HomeMade2F140_v2 (Autodesk Fusion 360 design; units mm, degrees)
part number: 2026-10-15-15-43-31-036
part number: 2026-10-15-15-43-44-268
part number: 2026-10-15-15-43-45-165
part number: 2026-10-15-15-43-48-577
part number: 2026-10-15-15-43-49-111
part number: 2026-10-15-15-43-49-328
part number: 2026-10-15-15-43-49-848
part number: 2026-10-15-15-43-50-479
part number: 2026-10-15-15-43-52-016
part number: 2026-10-15-15-43-53-608
part number: 2026-10-15-15-43-55-090
part number: 2026-10-15-15-43-57-573
part number: 2026-10-15-15-43-59-187
part number: 2026-10-15-15-44-01-030
part number: 2026-10-15-15-44-07-533
part number: 2026-10-15-15-44-10-409
part number: 2026-10-15-15-44-15-954
Autodesk Fusion 360 part; units mm, degrees
(part 1 of 3)
ref_plane "WorkPlane1" through (-36, 0, 0) normal (1, 0, 0) x (0, 1, 0) in component "Tower"
sketch "X00_add_rect" plane through (-36, 0, 0) normal (1, 0, 0) x (0, 0, -1) in component "Tower"
  line L0 (-36, -40.5) -> (-36, 40.5)
  line L1 (-36, 40.5) -> (-40, 40.5)
  line L2 (-40, 40.5) -> (-40, -40.5)
  line L3 (-40, -40.5) -> (-36, -40.5)
extrude "X00_add_rect (1)" add sketch "X00_add_rect" along normal blind 70 makes body 1 in component "Tower"
ref_plane "WorkPlane2" through (-5.25, 0, 0) normal (1, 0, 0) x (0, 1, 0) in component "Tower"
sketch "X01_cut_rect" plane through (-5.25, 0, 0) normal (1, 0, 0) x (0, 0, -1) in component "Tower"
  line L0 (-35, -26) -> (-35, 26)
  line L1 (-35, 26) -> (-41, 26)
  line L2 (-41, 26) -> (-41, -26)
  line L3 (-41, -26) -> (-35, -26)
extrude "X01_cut_rect (1)" cut sketch "X01_cut_rect" along normal blind 10.5 bodies 1 in component "Tower"
ref_plane "WorkPlane3" through (18.75, 0, 0) normal (1, 0, 0) x (0, 1, 0) in component "Tower"
sketch "X02_cut_rect" plane through (18.75, 0, 0) normal (1, 0, 0) x (0, 0, -1) in component "Tower"
  line L0 (-35, -37) -> (-35, -21)
  line L1 (-35, -21) -> (-41, -21)
  line L2 (-41, -21) -> (-41, -37)
  line L3 (-41, -37) -> (-35, -37)
extrude "X02_cut_rect (1)" cut sketch "X02_cut_rect" along normal blind 6.5 bodies 1 in component "Tower"
ref_plane "WorkPlane4" through (5, 0, 0) normal (1, 0, 0) x (0, 1, 0) in component "Tower"
sketch "X03_add_poly" plane through (5, 0, 0) normal (1, 0, 0) x (0, 0, -1) in component "Tower"
  line L0 (-40, -38) -> (-40, 38)
  line L1 (-40, 38) -> (-64, 38)
  line L2 (-64, 38) -> (-88, 14)
  line L3 (-88, 14) -> (-88, -14)
  line L4 (-88, -14) -> (-64, -38)
  line L5 (-64, -38) -> (-40, -38)
extrude "X03_add_poly (1)" add sketch "X03_add_poly" along normal blind 6 bodies 1 in component "Tower"
ref_plane "WorkPlane5" through (-11, 0, 0) normal (1, 0, 0) x (0, 1, 0) in component "Tower"
sketch "X04_add_poly" plane through (-11, 0, 0) normal (1, 0, 0) x (0, 0, -1) in component "Tower"
  line L0 (-40, -38) -> (-40, 38)
  line L1 (-40, 38) -> (-64, 38)
  line L2 (-64, 38) -> (-88, 14)
  line L3 (-88, 14) -> (-88, -14)
  line L4 (-88, -14) -> (-64, -38)
  line L5 (-64, -38) -> (-40, -38)
extrude "X04_add_poly (1)" add sketch "X04_add_poly" along normal blind 6 bodies 1 in component "Tower"
sketch "X05_add_rect" plane through (-11, 0, 0) normal (1, 0, 0) x (0, 0, -1) in component "Tower"
  line L0 (-85, -14) -> (-85, 14)
  line L1 (-85, 14) -> (-88, 14)
  line L2 (-88, 14) -> (-88, -14)
  line L3 (-88, -14) -> (-85, -14)
extrude "X05_add_rect (1)" add sketch "X05_add_rect" along normal blind 22 bodies 1 in component "Tower"
sketch "X06_cut_circle" plane through (-11, 0, 0) normal (1, 0, 0) x (0, 0, -1) in component "Tower"
  circle A0 centre (-54.905, -30.601) radius 1.65
extrude "X06_cut_circle (1)" cut sketch "X06_cut_circle" along normal blind 22 bodies 1 in component "Tower"
sketch "X07_cut_circle" plane through (-11, 0, 0) normal (1, 0, 0) x (0, 0, -1) in component "Tower"
  circle A0 centre (-54.905, 30.601) radius 1.65
extrude "X07_cut_circle (1)" cut sketch "X07_cut_circle" along normal blind 22 bodies 1 in component "Tower"
sketch "X08_cut_circle" plane through (-11, 0, 0) normal (1, 0, 0) x (0, 0, -1) in component "Tower"
  circle A0 centre (-61.42, -12.7) radius 1.65
extrude "X08_cut_circle (1)" cut sketch "X08_cut_circle" along normal blind 22 bodies 1 in component "Tower"
sketch "X09_cut_circle" plane through (-11, 0, 0) normal (1, 0, 0) x (0, 0, -1) in component "Tower"
  circle A0 centre (-61.42, 12.7) radius 1.65
extrude "X09_cut_circle (1)" cut sketch "X09_cut_circle" along normal blind 22 bodies 1 in component "Tower"
ref_plane "WorkPlane6" through (7.7, 0, 0) normal (1, 0, 0) x (0, 1, 0) in component "Tower"
sketch "X10_cut_circle" plane through (7.7, 0, 0) normal (1, 0, 0) x (0, 0, -1) in component "Tower"
  circle A0 centre (-54.905, -30.601) radius 3.1
extrude "X10_cut_circle (1)" cut sketch "X10_cut_circle" along normal blind 3.3 bodies 1 in component "Tower"
sketch "X11_cut_circle" plane through (-11, 0, 0) normal (1, 0, 0) x (0, 0, -1) in component "Tower"
  circle A0 centre (-54.905, 30.601) radius 3.1
extrude "X11_cut_circle (1)" cut sketch "X11_cut_circle" along normal blind 3.3 bodies 1 in component "Tower"
ref_plane "WorkPlane7" through (0, 0, 35.9) normal (0, 0, 1) x (1, 0, 0) in component "Tower"
sketch "Z00_cut_circle" plane through (0, 0, 35.9) normal (0, 0, 1) x (1, 0, 0) in component "Tower"
  circle A0 centre (-29, -31) radius 1.7
extrude "Z00_cut_circle (1)" cut sketch "Z00_cut_circle" along normal blind 4.2 bodies 1 in component "Tower"
sketch "Z01_cut_circle" plane through (0, 0, 35.9) normal (0, 0, 1) x (1, 0, 0) in component "Tower"
  circle A0 centre (-29, 31) radius 1.7
extrude "Z01_cut_circle (1)" cut sketch "Z01_cut_circle" along normal blind 4.2 bodies 1 in component "Tower"
sketch "Z02_cut_circle" plane through (0, 0, 35.9) normal (0, 0, 1) x (1, 0, 0) in component "Tower"
  circle A0 centre (27, 31) radius 1.7
extrude "Z02_cut_circle (1)" cut sketch "Z02_cut_circle" along normal blind 4.2 bodies 1 in component "Tower"
sketch "Z03_cut_circle" plane through (0, 0, 35.9) normal (0, 0, 1) x (1, 0, 0) in component "Tower"
  circle A0 centre (27, -10) radius 1.7
extrude "Z03_cut_circle (1)" cut sketch "Z03_cut_circle" along normal blind 4.2 bodies 1 in component "Tower"
ref_plane "WorkPlane1" through (-36, 0, 0) normal (1, 0, 0) x (0, 1, 0) in component "HousingBox"
sketch "X00_add_rect (2)" plane through (-36, 0, 0) normal (1, 0, 0) x (0, 0, -1) in component "HousingBox"
  line L0 (0, -40.5) -> (0, 40.5)
  line L1 (0, 40.5) -> (-4, 40.5)
  line L2 (-4, 40.5) -> (-4, -40.5)
  line L3 (-4, -40.5) -> (0, -40.5)
extrude "X00_add_rect (1)'" add sketch "X00_add_rect (2)" along normal blind 70 separate body makes body 2 in component "HousingBox"
sketch "X01_add_rect" plane through (-36, 0, 0) normal (1, 0, 0) x (0, 0, -1) in component "HousingBox"
  line L0 (0, -40.5) -> (0, 40.5)
  line L1 (0, 40.5) -> (-36, 40.5)
  line L2 (-36, 40.5) -> (-36, -40.5)
  line L3 (-36, -40.5) -> (0, -40.5)
extrude "X01_add_rect (1)" add sketch "X01_add_rect" along normal blind 3 bodies 2 in component "HousingBox"
ref_plane "WorkPlane2" through (31, 0, 0) normal (1, 0, 0) x (0, 1, 0) in component "HousingBox"
sketch "X02_add_rect" plane through (31, 0, 0) normal (1, 0, 0) x (0, 0, -1) in component "HousingBox"
  line L0 (0, -40.5) -> (0, 40.5)
  line L1 (0, 40.5) -> (-36, 40.5)
  line L2 (-36, 40.5) -> (-36, -40.5)
  line L3 (-36, -40.5) -> (0, -40.5)
extrude "X02_add_rect (1)" add sketch "X02_add_rect" along normal blind 3 bodies 2 in component "HousingBox"
sketch "X03_add_rect" plane through (-36, 0, 0) normal (1, 0, 0) x (0, 0, -1) in component "HousingBox"
  line L0 (0, -40.5) -> (0, -37.5)
  line L1 (0, -37.5) -> (-36, -37.5)
  line L2 (-36, -37.5) -> (-36, -40.5)
  line L3 (-36, -40.5) -> (0, -40.5)
extrude "X03_add_rect (1)" add sketch "X03_add_rect" along normal blind 70 bodies 2 in component "HousingBox"
sketch "X04_add_rect" plane through (-36, 0, 0) normal (1, 0, 0) x (0, 0, -1) in component "HousingBox"
  line L0 (0, 37.5) -> (0, 40.5)
  line L1 (0, 40.5) -> (-36, 40.5)
  line L2 (-36, 40.5) -> (-36, 37.5)
  line L3 (-36, 37.5) -> (0, 37.5)
extrude "X04_add_rect (1)" add sketch "X04_add_rect" along normal blind 70 bodies 2 in component "HousingBox"
ref_plane "WorkPlane3" through (-1.5, 0, 0) normal (1, 0, 0) x (0, 1, 0) in component "HousingBox"
sketch "X05_add_rect (2)" plane through (-1.5, 0, 0) normal (1, 0, 0) x (0, 0, -1) in component "HousingBox"
  line L0 (-4, -37.5) -> (-4, -24.7488)
  line L1 (-4, -24.7488) -> (-27.5, -24.7488)
  line L2 (-27.5, -24.7488) -> (-27.5, -37.5)
  line L3 (-27.5, -37.5) -> (-4, -37.5)
extrude "X05_add_rect (1)'" add sketch "X05_add_rect (2)" along normal blind 5 bodies 2 in component "HousingBox"
sketch "X06_add_rect" plane through (-1.5, 0, 0) normal (1, 0, 0) x (0, 0, -1) in component "HousingBox"
  line L0 (-4, 15.7512) -> (-4, 37.5)
  line L1 (-4, 37.5) -> (-27.5, 37.5)
  line L2 (-27.5, 37.5) -> (-27.5, 15.7512)
  line L3 (-27.5, 15.7512) -> (-4, 15.7512)
extrude "X06_add_rect (1)" add sketch "X06_add_rect" along normal blind 5 bodies 2 in component "HousingBox"
sketch "X07_cut_circle (2)" plane through (-1.5, 0, 0) normal (1, 0, 0) x (0, 0, -1) in component "HousingBox"
  circle A0 centre (-12.55, -28.7988) radius 1.7
extrude "X07_cut_circle (1)'" cut sketch "X07_cut_circle (2)" along normal blind 5 bodies 2 in component "HousingBox"
sketch "X08_cut_circle (2)" plane through (-1.5, 0, 0) normal (1, 0, 0) x (0, 0, -1) in component "HousingBox"
  circle A0 centre (-22.45, -28.7988) radius 1.7
extrude "X08_cut_circle (1)'" cut sketch "X08_cut_circle (2)" along normal blind 5 bodies 2 in component "HousingBox"
sketch "X09_cut_circle (2)" plane through (-1.5, 0, 0) normal (1, 0, 0) x (0, 0, -1) in component "HousingBox"
  circle A0 centre (-12.55, 19.8012) radius 1.7
extrude "X09_cut_circle (1)'" cut sketch "X09_cut_circle (2)" along normal blind 5 bodies 2 in component "HousingBox"
sketch "X10_cut_circle (2)" plane through (-1.5, 0, 0) normal (1, 0, 0) x (0, 0, -1) in component "HousingBox"
  circle A0 centre (-22.45, 19.8012) radius 1.7
extrude "X10_cut_circle (1)'" cut sketch "X10_cut_circle (2)" along normal blind 5 bodies 2 in component "HousingBox"
ref_plane "WorkPlane4" through (-33.5, 0, 0) normal (1, 0, 0) x (0, 1, 0) in component "HousingBox"
sketch "X11_add_rect" plane through (-33.5, 0, 0) normal (1, 0, 0) x (0, 0, -1) in component "HousingBox"
  line L0 (-4, -35.5) -> (-4, -26.5)
  line L1 (-4, -26.5) -> (-36, -26.5)
  line L2 (-36, -26.5) -> (-36, -35.5)
  line L3 (-36, -35.5) -> (-4, -35.5)
extrude "X11_add_rect (1)" add sketch "X11_add_rect" along normal blind 9 bodies 2 in component "HousingBox"
sketch "X12_add_rect" plane through (-33.5, 0, 0) normal (1, 0, 0) x (0, 0, -1) in component "HousingBox"
  line L0 (-4, 26.5) -> (-4, 35.5)
  line L1 (-4, 35.5) -> (-36, 35.5)
  line L2 (-36, 35.5) -> (-36, 26.5)
  line L3 (-36, 26.5) -> (-4, 26.5)
extrude "X12_add_rect (1)" add sketch "X12_add_rect" along normal blind 9 bodies 2 in component "HousingBox"
ref_plane "WorkPlane5" through (22.5, 0, 0) normal (1, 0, 0) x (0, 1, 0) in component "HousingBox"
sketch "X13_add_rect" plane through (22.5, 0, 0) normal (1, 0, 0) x (0, 0, -1) in component "HousingBox"
  line L0 (-4, 26.5) -> (-4, 35.5)
  line L1 (-4, 35.5) -> (-36, 35.5)
  line L2 (-36, 35.5) -> (-36, 26.5)
  line L3 (-36, 26.5) -> (-4, 26.5)
extrude "X13_add_rect (1)" add sketch "X13_add_rect" along normal blind 9 bodies 2 in component "HousingBox"
sketch "X14_add_rect" plane through (22.5, 0, 0) normal (1, 0, 0) x (0, 0, -1) in component "HousingBox"
  line L0 (-4, -14.5) -> (-4, -5.5)
  line L1 (-4, -5.5) -> (-36, -5.5)
  line L2 (-36, -5.5) -> (-36, -14.5)
  line L3 (-36, -14.5) -> (-4, -14.5)
extrude "X14_add_rect (1)" add sketch "X14_add_rect" along normal blind 9 bodies 2 in component "HousingBox"
ref_plane "WorkPlane6" through (-36.1, 0, 0) normal (1, 0, 0) x (0, 1, 0) in component "HousingBox"
sketch "X15_cut_hull" plane through (-36.1, 0, 0) normal (1, 0, 0) x (0, 0, -1) in component "HousingBox"
  line L0 (-8, 19.5012) -> (-8, 27.5012)
  arc A0 (-8, 27.5012) -> (-17, 27.5012) centre (-12.5, 27.5012) ccw
  line L1 (-17, 27.5012) -> (-17, 19.5012)
  arc A1 (-17, 19.5012) -> (-8, 19.5012) centre (-12.5, 19.5012) ccw
extrude "X15_cut_hull (1)" cut sketch "X15_cut_hull" along normal blind 3.2 bodies 2 in component "HousingBox"
ref_plane "WorkPlane7" through (0, 0, 22) normal (0, 0, 1) x (1, 0, 0) in component "HousingBox"
sketch "Z00_cut_circle (2)" plane through (0, 0, 22) normal (0, 0, 1) x (1, 0, 0) in component "HousingBox"
  circle A0 centre (-29, -31) radius 1.7
extrude "Z00_cut_circle (1)'" cut sketch "Z00_cut_circle (2)" along normal blind 14.1 bodies 2 in component "HousingBox"
ref_plane "WorkPlane8" through (0, 0, 29.5) normal (0, 0, 1) x (1, 0, 0) in component "HousingBox"
sketch "Z01_cut_hex" plane through (0, 0, 29.5) normal (0, 0, 1) x (1, 0, 0) in component "HousingBox"
  line L0 (-28.2546, -27.7946) -> (-31.4032, -28.7518)
  line L1 (-31.4032, -28.7518) -> (-32.1486, -31.9572)
  line L2 (-32.1486, -31.9572) -> (-29.7454, -34.2054)
  line L3 (-29.7454, -34.2054) -> (-26.5968, -33.2482)
  line L4 (-26.5968, -33.2482) -> (-25.8514, -30.0428)
  line L5 (-25.8514, -30.0428) -> (-28.2546, -27.7946)
extrude "Z01_cut_hex (1)" cut sketch "Z01_cut_hex" along normal blind 4.2 bodies 2 in component "HousingBox"
sketch "Z02_cut_poly" plane through (0, 0, 29.5) normal (0, 0, 1) x (1, 0, 0) in component "HousingBox"
  line L0 (-31.0813, -29.053) -> (-10.5866, -7.1449)
  line L1 (-10.5866, -7.1449) -> (-6.424, -11.0389)
  line L2 (-6.424, -11.0389) -> (-26.9187, -32.947)
  line L3 (-26.9187, -32.947) -> (-31.0813, -29.053)
extrude "Z02_cut_poly (1)" cut sketch "Z02_cut_poly" along normal blind 4.2 bodies 2 in component "HousingBox"
sketch "Z03_cut_circle (2)" plane through (0, 0, 22) normal (0, 0, 1) x (1, 0, 0) in component "HousingBox"
  circle A0 centre (-29, 31) radius 1.7
extrude "Z03_cut_circle (1)'" cut sketch "Z03_cut_circle (2)" along normal blind 14.1 bodies 2 in component "HousingBox"
sketch "Z04_cut_hex" plane through (0, 0, 29.5) normal (0, 0, 1) x (1, 0, 0) in component "HousingBox"
  line L0 (-25.8514, 30.0428) -> (-26.5968, 33.2482)
  line L1 (-26.5968, 33.2482) -> (-29.7454, 34.2054)
  line L2 (-29.7454, 34.2054) -> (-32.1486, 31.9572)
  line L3 (-32.1486, 31.9572) -> (-31.4032, 28.7518)
  line L4 (-31.4032, 28.7518) -> (-28.2546, 27.7946)
  line L5 (-28.2546, 27.7946) -> (-25.8514, 30.0428)
extrude "Z04_cut_hex (1)" cut sketch "Z04_cut_hex" along normal blind 4.2 bodies 2 in component "HousingBox"
sketch "Z05_cut_poly" plane through (0, 0, 29.5) normal (0, 0, 1) x (1, 0, 0) in component "HousingBox"
  line L0 (-26.9187, 32.947) -> (-6.424, 11.0389)
  line L1 (-6.424, 11.0389) -> (-10.5866, 7.1449)
  line L2 (-10.5866, 7.1449) -> (-31.0813, 29.053)
  line L3 (-31.0813, 29.053) -> (-26.9187, 32.947)
extrude "Z05_cut_poly (1)" cut sketch "Z05_cut_poly" along normal blind 4.2 bodies 2 in component "HousingBox"
sketch "Z06_cut_circle" plane through (0, 0, 22) normal (0, 0, 1) x (1, 0, 0) in component "HousingBox"
  circle A0 centre (27, 31) radius 1.7
extrude "Z06_cut_circle (1)" cut sketch "Z06_cut_circle" along normal blind 14.1 bodies 2 in component "HousingBox"
sketch "Z07_cut_hex" plane through (0, 0, 29.5) normal (0, 0, 1) x (1, 0, 0) in component "HousingBox"
  line L0 (26.369, 27.7702) -> (29.4816, 28.8386)
  line L1 (29.4816, 28.8386) -> (30.1126, 32.0684)
  line L2 (30.1126, 32.0684) -> (27.631, 34.2298)
  line L3 (27.631, 34.2298) -> (24.5184, 33.1614)
  line L4 (24.5184, 33.1614) -> (23.8874, 29.9316)
  line L5 (23.8874, 29.9316) -> (26.369, 27.7702)
extrude "Z07_cut_hex (1)" cut sketch "Z07_cut_hex" along normal blind 4.2 bodies 2 in component "HousingBox"
sketch "Z08_cut_poly" plane through (0, 0, 29.5) normal (0, 0, 1) x (1, 0, 0) in component "HousingBox"
  line L0 (29.1491, 29.1282) -> (9.4457, 6.5057)
  line L1 (9.4457, 6.5057) -> (5.1474, 10.2494)
  line L2 (5.1474, 10.2494) -> (24.8509, 32.8718)
  line L3 (24.8509, 32.8718) -> (29.1491, 29.1282)
extrude "Z08_cut_poly (1)" cut sketch "Z08_cut_poly" along normal blind 4.2 bodies 2 in component "HousingBox"
sketch "Z09_cut_circle" plane through (0, 0, 22) normal (0, 0, 1) x (1, 0, 0) in component "HousingBox"
  circle A0 centre (27, -10) radius 1.7
extrude "Z09_cut_circle (1)" cut sketch "Z09_cut_circle" along normal blind 14.1 bodies 2 in component "HousingBox"
sketch "Z10_cut_hex" plane through (0, 0, 29.5) normal (0, 0, 1) x (1, 0, 0) in component "HousingBox"
  line L0 (23.7559, -10.5532) -> (25.857, -13.086)
  line L1 (25.857, -13.086) -> (29.1011, -12.5329)
  line L2 (29.1011, -12.5329) -> (30.2441, -9.4468)
  line L3 (30.2441, -9.4468) -> (28.143, -6.914)
  line L4 (28.143, -6.914) -> (24.8989, -7.4671)
  line L5 (24.8989, -7.4671) -> (23.7559, -10.5532)
extrude "Z10_cut_hex (1)" cut sketch "Z10_cut_hex" along normal blind 4.2 bodies 2 in component "HousingBox"
sketch "Z11_cut_poly" plane through (0, 0, 29.5) normal (0, 0, 1) x (1, 0, 0) in component "HousingBox"
  line L0 (26.0102, -12.6726) -> (-2.1223, -2.2532)
  line L1 (-2.1223, -2.2532) -> (-0.1426, 3.092)
  line L2 (-0.1426, 3.092) -> (27.9898, -7.3274)
  line L3 (27.9898, -7.3274) -> (26.0102, -12.6726)
extrude "Z11_cut_poly (1)" cut sketch "Z11_cut_poly" along normal blind 4.2 bodies 2 in component "HousingBox"
ref_plane "WorkPlane9" through (0, 0, -0.1) normal (0, 0, 1) x (1, 0, 0) in component "HousingBox"
sketch "Z12_cut_circle" plane through (0, 0, -0.1) normal (0, 0, 1) x (1, 0, 0) in component "HousingBox"
  circle A0 centre (26.8, 11.1) radius 1.7
extrude "Z12_cut_circle (1)" cut sketch "Z12_cut_circle" along normal blind 4.2 bodies 2 in component "HousingBox"
sketch "Z13_cut_circle" plane through (0, 0, -0.1) normal (0, 0, 1) x (1, 0, 0) in component "HousingBox"
  circle A0 centre (-11.1, 26.8) radius 1.7
extrude "Z13_cut_circle (1)" cut sketch "Z13_cut_circle" along normal blind 4.2 bodies 2 in component "HousingBox"
sketch "Z14_cut_circle" plane through (0, 0, -0.1) normal (0, 0, 1) x (1, 0, 0) in component "HousingBox"
  circle A0 centre (-18, -28.5) radius 1.7
extrude "Z14_cut_circle (1)" cut sketch "Z14_cut_circle" along normal blind 4.2 bodies 2 in component "HousingBox"
sketch "Z15_cut_circle" plane through (0, 0, -0.1) normal (0, 0, 1) x (1, 0, 0) in component "HousingBox"
  circle A0 centre (11.1, -26.8) radius 1.7
extrude "Z15_cut_circle (1)" cut sketch "Z15_cut_circle" along normal blind 4.2 bodies 2 in component "HousingBox"
ref_plane "WorkPlane1" through (-32, 0, 0) normal (1, 0, 0) x (0, 1, 0) in component "Servo_D5545GS"
sketch "X00_add_rect (3)" plane through (-32, 0, 0) normal (1, 0, 0) x (0, 0, -1) in component "Servo_D5545GS"
  line L0 (-7.5, -24.4988) -> (-7.5, 15.5012)
  line L1 (-7.5, 15.5012) -> (-27.5, 15.5012)
  line L2 (-27.5, 15.5012) -> (-27.5, -24.4988)
  line L3 (-27.5, -24.4988) -> (-7.5, -24.4988)
extrude "X00_add_rect (1)''" add sketch "X00_add_rect (3)" along normal blind 40.5 separate body makes body 3 in component "Servo_D5545GS"
ref_plane "WorkPlane2" through (-4.7, 0, 0) normal (1, 0, 0) x (0, 1, 0) in component "Servo_D5545GS"
sketch "X01_add_rect (2)" plane through (-4.7, 0, 0) normal (1, 0, 0) x (0, 0, -1) in component "Servo_D5545GS"
  line L0 (-7.5, -31.4988) -> (-7.5, 22.5012)
  line L1 (-7.5, 22.5012) -> (-27.5, 22.5012)
  line L2 (-27.5, 22.5012) -> (-27.5, -31.4988)
  line L3 (-27.5, -31.4988) -> (-7.5, -31.4988)
extrude "X01_add_rect (1)'" add sketch "X01_add_rect (2)" along normal blind 3.2 bodies 3 in component "Servo_D5545GS"
ref_plane "WorkPlane3" through (8.5, 0, 0) normal (1, 0, 0) x (0, 1, 0) in component "Servo_D5545GS"
sketch "X02_add_circle" plane through (8.5, 0, 0) normal (1, 0, 0) x (0, 0, -1) in component "Servo_D5545GS"
  circle A0 centre (-17.5, -14.6988) radius 3
extrude "X02_add_circle (1)" add sketch "X02_add_circle" along normal blind 2.5 bodies 3 in component "Servo_D5545GS"
ref_plane "WorkPlane1" through (11, 0, 0) normal (1, 0, 0) x (0, 1, 0) in component "ServoHorn_Ref"
sketch "X00_add_circle" plane through (11, 0, 0) normal (1, 0, 0) x (0, 0, -1) in component "ServoHorn_Ref"
  circle A0 centre (-17.5, -14.6988) radius 12.5
extrude "X00_add_circle (1)" add sketch "X00_add_circle" along normal blind 3 separate body makes body 4 in component "ServoHorn_Ref"
ref_plane "WorkPlane1" through (14, 0, 0) normal (1, 0, 0) x (0, 1, 0) in component "Crank"
sketch "X00_add_hull" plane through (14, 0, 0) normal (1, 0, 0) x (0, 0, -1) in component "Crank"
  line L0 (-6.6027, -30.2631) -> (-4.6321, -16.5476)
  arc A0 (-4.6321, -16.5476) -> (-25.535, -24.9183) centre (-17.5, -14.6988) ccw
  line L1 (-25.535, -24.9183) -> (-14.6423, -33.4827)
  arc A1 (-14.6423, -33.4827) -> (-6.6027, -30.2631) centre (-11.5519, -29.5521) ccw
extrude "X00_add_hull (1)" add sketch "X00_add_hull" along normal blind 5 separate body makes body 5 in component "Crank"
sketch "X01_cut_circle" plane through (14, 0, 0) normal (1, 0, 0) x (0, 0, -1) in component "Crank"
  circle A0 centre (-17.5, -14.6988) radius 3.6
extrude "X01_cut_circle (1)" cut sketch "X01_cut_circle" along normal blind 5 bodies 5 in component "Crank"
sketch "X02_cut_circle" plane through (14, 0, 0) normal (1, 0, 0) x (0, 0, -1) in component "Crank"
  circle A0 centre (-11.5519, -29.5521) radius 1.65
extrude "X02_cut_circle (1)" cut sketch "X02_cut_circle" along normal blind 5 bodies 5 in component "Crank"
ref_plane "WorkPlane1" through (19.5, 0, 0) normal (1, 0, 0) x (0, 1, 0) in component "Rod"
sketch "X00_add_hull (2)" plane through (19.5, 0, 0) normal (1, 0, 0) x (0, 0, -1) in component "Rod"
  line L0 (-55.2565, -34.6145) -> (-11.5447, -34.5521)
  arc A0 (-11.5447, -34.5521) -> (-11.559, -24.5521) centre (-11.5519, -29.5521) ccw
  line L1 (-11.559, -24.5521) -> (-55.2708, -24.6145)
  arc A1 (-55.2708, -24.6145) -> (-55.2565, -34.6145) centre (-55.2636, -29.6145) ccw
extrude "X00_add_hull (1)'" add sketch "X00_add_hull (2)" along normal blind 5 separate body makes body 6 in component "Rod"
sketch "X01_cut_circle (2)" plane through (19.5, 0, 0) normal (1, 0, 0) x (0, 0, -1) in component "Rod"
  circle A0 centre (-11.5519, -29.5521) radius 1.65
extrude "X01_cut_circle (1)'" cut sketch "X01_cut_circle (2)" along normal blind 5 bodies 6 in component "Rod"
sketch "X02_cut_circle (2)" plane through (19.5, 0, 0) normal (1, 0, 0) x (0, 0, -1) in component "Rod"
  circle A0 centre (-55.2636, -29.6145) radius 1.65
extrude "X02_cut_circle (1)'" cut sketch "X02_cut_circle (2)" along normal blind 5 bodies 6 in component "Rod"
ref_plane "WorkPlane1" through (-4.75, 0, 0) normal (1, 0, 0) x (0, 1, 0) in component "OuterKnuckle_L"
sketch "X00_add_circle (2)" plane through (-4.75, 0, 0) normal (1, 0, 0) x (0, 0, -1) in component "OuterKnuckle_L"
  circle A0 centre (-54.905, -30.601) radius 9
extrude "X00_add_circle (1)'" add sketch "X00_add_circle (2)" along normal blind 9.5 separate body makes body 7 in component "OuterKnuckle_L"
sketch "X01_add_hull" plane through (-4.75, 0, 0) normal (1, 0, 0) x (0, 0, -1) in component "OuterKnuckle_L"
  line L0 (-58.2433, -71.5153) -> (-49.0042, -67.6891)
  arc A0 (-49.0042, -67.6891) -> (-45.3076, -61.8413) centre (-51.2999, -62.1457) ccw
  line L1 (-45.3076, -61.8413) -> (-46.9153, -30.1951)
  arc A1 (-46.9153, -30.1951) -> (-62.8633, -29.7857) centre (-54.905, -30.601) ccw
  line L2 (-62.8633, -29.7857) -> (-66.5078, -65.3604)
  arc A2 (-66.5078, -65.3604) -> (-58.2433, -71.5153) centre (-60.539, -65.9718) ccw
extrude "X01_add_hull (1)" add sketch "X01_add_hull" along normal blind 9.5 bodies 7 in component "OuterKnuckle_L"
sketch "X02_add_gear" plane through (-4.75, 0, 0) normal (1, 0, 0) x (0, 0, -1) in component "OuterKnuckle_L"
  line L0 (-54.905, -30.601) -> (-47.1467, -3.3332)
  arc A0 (-47.1467, -3.3332) -> (-48.0936, -3.0814) centre (-54.905, -30.601) ccw
  line L1 (-48.0936, -3.0814) -> (-47.9964, -2.6887)
  spline S0 degree 5 poles (-47.9964, -2.6887) (-47.9922, -2.6642) (-47.9841, -2.6151) (-47.973, -2.5413) (-47.9601, -2.4426) (-47.9472, -2.3186) (-47.9375, -2.194) (-47.931, -2.0688) (-47.9275, -1.943) (-47.9268, -1.8168) (-47.9287, -1.6902) (-47.9328, -1.5632) (-47.9389, -1.4359) (-47.9469, -1.3084) (-47.9565, -1.1807) (-47.9678, -1.0529) (-47.9808, -0.9248) (-47.9954, -0.7966) (-48.0117, -0.6683) (-48.0296, -0.5398) (-48.0492, -0.4111) (-48.0703, -0.2823) (-48.0929, -0.1535) (-48.1169, -0.0245) (-48.1424, 0.1045) (-48.1692, 0.2336) (-48.1973, 0.3628) (-48.2268, 0.4919) (-48.2577, 0.6211) (-48.2899, 0.7504) (-48.3234, 0.8796) (-48.3513, 0.983) (-48.3727, 1.0606) (-48.3873, 1.1123) (-48.3947, 1.1382) knots 0 0 0 0 0 0 0.033333 0.066667 0.1 0.133333 0.166667 0.2 0.233333 0.266667 0.3 0.333333 0.366667 0.4 0.433333 0.466667 0.5 0.533333 0.566667 0.6 0.633333 0.666667 0.7 0.733333 0.766667 0.8 0.833333 0.866667 0.9 0.933333 0.966667 1 1 1 1 1 1
  arc A1 (-48.3947, 1.1382) -> (-49.5102, 1.3467) centre (-54.905, -30.601) ccw
  spline S1 degree 5 poles (-49.5102, 1.3467) (-49.5264, 1.3252) (-49.5587, 1.2823) (-49.6067, 1.2177) (-49.67, 1.1313) (-49.748, 1.0229) (-49.8247, 0.914) (-49.9001, 0.8047) (-49.9743, 0.6949) (-50.0472, 0.5847) (-50.1189, 0.474) (-50.1892, 0.3629) (-50.2582, 0.2513) (-50.3258, 0.1393) (-50.392, 0.0268) (-50.4567, -0.0861) (-50.5199, -0.1994) (-50.5815, -0.3132) (-50.6414, -0.4275) (-50.6997, -0.5422) (-50.7565, -0.6573) (-50.8116, -0.7729) (-50.865, -0.8889) (-50.9167, -1.0054) (-50.9664, -1.1223) (-51.0139, -1.2397) (-51.0589, -1.3577) (-51.101, -1.4762) (-51.1402, -1.5953) (-51.1762, -1.715) (-51.209, -1.8353) (-51.2326, -1.932) (-51.2489, -2.0048) (-51.2591, -2.0535) (-51.264, -2.0779) knots 0 0 0 0 0 0 0.033333 0.066667 0.1 0.133333 0.166667 0.2 0.233333 0.266667 0.3 0.333333 0.366667 0.4 0.433333 0.466667 0.5 0.533333 0.566667 0.6 0.633333 0.666667 0.7 0.733333 0.766667 0.8 0.833333 0.866667 0.9 0.933333 0.966667 1 1 1 1 1 1
  line L2 (-51.264, -2.0779) -> (-51.3153, -2.4792)
  arc A2 (-51.3153, -2.4792) -> (-53.2663, -2.2984) centre (-54.905, -30.601) ccw
  line L3 (-53.2663, -2.2984) -> (-53.2429, -1.8945)
  spline S2 degree 5 poles (-53.2429, -1.8945) (-53.2432, -1.8696) (-53.2443, -1.8199) (-53.2469, -1.7454) (-53.2524, -1.6459) (-53.2625, -1.5217) (-53.2759, -1.3974) (-53.2925, -1.2731) (-53.3122, -1.1489) (-53.3347, -1.0247) (-53.3598, -0.9005) (-53.3872, -0.7765) (-53.4166, -0.6525) (-53.4478, -0.5286) (-53.4808, -0.4049) (-53.5154, -0.2813) (-53.5516, -0.1578) (-53.5896, -0.0345) (-53.6292, 0.0887) (-53.6705, 0.2117) (-53.7133, 0.3346) (-53.7577, 0.4573) (-53.8036, 0.5798) (-53.8509, 0.7022) (-53.8996, 0.8244) (-53.9497, 0.9463) (-54.0011, 1.0681) (-54.0539, 1.1896) (-54.1079, 1.3109) (-54.1633, 1.4321) (-54.22, 1.5529) (-54.2664, 1.6495) (-54.3018, 1.7218) (-54.3256, 1.77) (-54.3376, 1.794) knots 0 0 0 0 0 0 0.033333 0.066667 0.1 0.133333 0.166667 0.2 0.233333 0.266667 0.3 0.333333 0.366667 0.4 0.433333 0.466667 0.5 0.533333 0.566667 0.6 0.633333 0.666667 0.7 0.733333 0.766667 0.8 0.833333 0.866667 0.9 0.933333 0.966667 1 1 1 1 1 1
  arc A3 (-54.3376, 1.794) -> (-55.4724, 1.794) centre (-54.905, -30.601) ccw
  spline S3 degree 5 poles (-55.4724, 1.794) (-55.4844, 1.77) (-55.5082, 1.7218) (-55.5436, 1.6495) (-55.59, 1.5529) (-55.6467, 1.4321) (-55.7021, 1.3109) (-55.7561, 1.1896) (-55.8089, 1.0681) (-55.8603, 0.9463) (-55.9104, 0.8244) (-55.9591, 0.7022) (-56.0064, 0.5798) (-56.0523, 0.4573) (-56.0967, 0.3346) (-56.1395, 0.2117) (-56.1808, 0.0887) (-56.2204, -0.0345) (-56.2584, -0.1578) (-56.2946, -0.2813) (-56.3292, -0.4049) (-56.3622, -0.5286) (-56.3934, -0.6525) (-56.4228, -0.7765) (-56.4502, -0.9005) (-56.4753, -1.0247) (-56.4978, -1.1489) (-56.5175, -1.2731) (-56.5341, -1.3974) (-56.5475, -1.5217) (-56.5576, -1.6459) (-56.5631, -1.7454) (-56.5657, -1.8199) (-56.5668, -1.8696) (-56.5671, -1.8945) knots 0 0 0 0 0 0 0.033333 0.066667 0.1 0.133333 0.166667 0.2 0.233333 0.266667 0.3 0.333333 0.366667 0.4 0.433333 0.466667 0.5 0.533333 0.566667 0.6 0.633333 0.666667 0.7 0.733333 0.766667 0.8 0.833333 0.866667 0.9 0.933333 0.966667 1 1 1 1 1 1
  line L4 (-56.5671, -1.8945) -> (-56.5437, -2.2984)
  arc A4 (-56.5437, -2.2984) -> (-58.4947, -2.4792) centre (-54.905, -30.601) ccw
  line L5 (-58.4947, -2.4792) -> (-58.546, -2.0779)
  spline S4 degree 5 poles (-58.546, -2.0779) (-58.5509, -2.0535) (-58.5611, -2.0048) (-58.5774, -1.932) (-58.601, -1.8353) (-58.6338, -1.715) (-58.6698, -1.5953) (-58.709, -1.4762) (-58.7511, -1.3577) (-58.7961, -1.2397) (-58.8436, -1.1223) (-58.8933, -1.0054) (-58.945, -0.8889) (-58.9984, -0.7729) (-59.0535, -0.6573) (-59.1103, -0.5422) (-59.1686, -0.4275) (-59.2285, -0.3132) (-59.2901, -0.1994) (-59.3533, -0.0861) (-59.418, 0.0268) (-59.4842, 0.1393) (-59.5518, 0.2513) (-59.6208, 0.3629) (-59.6911, 0.474) (-59.7628, 0.5847) (-59.8357, 0.6949) (-59.9099, 0.8047) (-59.9853, 0.914) (-60.062, 1.0229) (-60.14, 1.1313) (-60.2033, 1.2177) (-60.2513, 1.2823) (-60.2836, 1.3252) (-60.2998, 1.3467) knots 0 0 0 0 0 0 0.033333 0.066667 0.1 0.133333 0.166667 0.2 0.233333 0.266667 0.3 0.333333 0.366667 0.4 0.433333 0.466667 0.5 0.533333 0.566667 0.6 0.633333 0.666667 0.7 0.733333 0.766667 0.8 0.833333 0.866667 0.9 0.933333 0.966667 1 1 1 1 1 1
  arc A5 (-60.2998, 1.3467) -> (-61.4153, 1.1382) centre (-54.905, -30.601) ccw
  spline S5 degree 5 poles (-61.4153, 1.1382) (-61.4227, 1.1123) (-61.4373, 1.0606) (-61.4587, 0.983) (-61.4866, 0.8796) (-61.5201, 0.7504) (-61.5523, 0.6211) (-61.5832, 0.4919) (-61.6127, 0.3628) (-61.6408, 0.2336) (-61.6676, 0.1045) (-61.6931, -0.0245) (-61.7171, -0.1535) (-61.7397, -0.2823) (-61.7608, -0.4111) (-61.7804, -0.5398) (-61.7983, -0.6683) (-61.8146, -0.7966) (-61.8292, -0.9248) (-61.8422, -1.0529) (-61.8535, -1.1807) (-61.8631, -1.3084) (-61.8711, -1.4359) (-61.8772, -1.5632) (-61.8813, -1.6902) (-61.8832, -1.8168) (-61.8825, -1.943) (-61.879, -2.0688) (-61.8725, -2.194) (-61.8628, -2.3186) (-61.8499, -2.4426) (-61.837, -2.5413) (-61.8259, -2.6151) (-61.8178, -2.6642) (-61.8136, -2.6887) knots 0 0 0 0 0 0 0.033333 0.066667 0.1 0.133333 0.166667 0.2 0.233333 0.266667 0.3 0.333333 0.366667 0.4 0.433333 0.466667 0.5 0.533333 0.566667 0.6 0.633333 0.666667 0.7 0.733333 0.766667 0.8 0.833333 0.866667 0.9 0.933333 0.966667 1 1 1 1 1 1
  line L6 (-61.8136, -2.6887) -> (-61.7164, -3.0814)
  arc A6 (-61.7164, -3.0814) -> (-63.601, -3.6176) centre (-54.905, -30.601) ccw
  line L7 (-63.601, -3.6176) -> (-63.7251, -3.2325)
  spline S6 degree 5 poles (-63.7251, -3.2325) (-63.7344, -3.2095) (-63.7534, -3.1635) (-63.7828, -3.095) (-63.8238, -3.0042) (-63.8781, -2.892) (-63.9355, -2.781) (-63.9959, -2.6711) (-64.0591, -2.5623) (-64.125, -2.4547) (-64.1932, -2.348) (-64.2636, -2.2422) (-64.3358, -2.1372) (-64.4096, -2.033) (-64.485, -1.9295) (-64.562, -1.8267) (-64.6404, -1.7247) (-64.7203, -1.6234) (-64.8017, -1.5228) (-64.8847, -1.423) (-64.969, -1.3239) (-65.0548, -1.2255) (-65.1418, -1.1279) (-65.2301, -1.0309) (-65.3197, -0.9345) (-65.4104, -0.8389) (-65.5023, -0.7439) (-65.5954, -0.6497) (-65.6897, -0.5561) (-65.7851, -0.4631) (-65.8816, -0.3709) (-65.9598, -0.2976) (-66.0188, -0.243) (-66.0585, -0.2067) (-66.0783, -0.1886) knots 0 0 0 0 0 0 0.033333 0.066667 0.1 0.133333 0.166667 0.2 0.233333 0.266667 0.3 0.333333 0.366667 0.4 0.433333 0.466667 0.5 0.533333 0.566667 0.6 0.633333 0.666667 0.7 0.733333 0.766667 0.8 0.833333 0.866667 0.9 0.933333 0.966667 1 1 1 1 1 1
  arc A7 (-66.0783, -0.1886) -> (-67.1365, -0.5985) centre (-54.905, -30.601) ccw
  spline S7 degree 5 poles (-67.1365, -0.5985) (-67.139, -0.6253) (-67.1438, -0.6788) (-67.1507, -0.759) (-67.1591, -0.8658) (-67.1683, -0.999) (-67.1762, -1.1319) (-67.1828, -1.2646) (-67.188, -1.397) (-67.192, -1.5291) (-67.1946, -1.6609) (-67.1959, -1.7924) (-67.1958, -1.9236) (-67.1944, -2.0544) (-67.1914, -2.1849) (-67.187, -2.315) (-67.1811, -2.4446) (-67.1735, -2.5738) (-67.1643, -2.7025) (-67.1535, -2.8307) (-67.1411, -2.9585) (-67.1272, -3.0857) (-67.1115, -3.2125) (-67.0942, -3.3387) (-67.0749, -3.4643) (-67.0534, -3.5892) (-67.0296, -3.7131) (-67.003, -3.8361) (-66.9736, -3.9579) (-66.9412, -4.0787) (-66.9058, -4.1982) (-66.8749, -4.2929) (-66.8504, -4.3633) (-66.8335, -4.4101) (-66.8249, -4.4334) knots 0 0 0 0 0 0 0.033333 0.066667 0.1 0.133333 0.166667 0.2 0.233333 0.266667 0.3 0.333333 0.366667 0.4 0.433333 0.466667 0.5 0.533333 0.566667 0.6 0.633333 0.666667 0.7 0.733333 0.766667 0.8 0.833333 0.866667 0.9 0.933333 0.966667 1 1 1 1 1 1
  line L8 (-66.8249, -4.4334) -> (-66.6572, -4.8016)
  arc A8 (-66.6572, -4.8016) -> (-68.4111, -5.675) centre (-54.905, -30.601) ccw
  line L9 (-68.4111, -5.675) -> (-68.6039, -5.3192)
  spline S8 degree 5 poles (-68.6039, -5.3192) (-68.6173, -5.2983) (-68.6444, -5.2566) (-68.6858, -5.1946) (-68.7428, -5.1129) (-68.8168, -5.0126) (-68.8937, -4.914) (-68.9732, -4.8171) (-69.0553, -4.7218) (-69.1399, -4.6281) (-69.2266, -4.5357) (-69.3151, -4.4447) (-69.4054, -4.3547) (-69.4972, -4.2659) (-69.5903, -4.178) (-69.6848, -4.0911) (-69.7806, -4.0052) (-69.8778, -3.9203) (-69.9763, -3.8365) (-70.0762, -3.7536) (-70.1773, -3.6717) (-70.2797, -3.5907) (-70.3832, -3.5107) (-70.4878, -3.4316) (-70.5935, -3.3534) (-70.7003, -3.276) (-70.8081, -3.1996) (-70.917, -3.124) (-71.0268, -3.0493) (-71.1377, -2.9755) (-71.2495, -2.9026) (-71.3398, -2.8449) (-71.4079, -2.802) (-71.4535, -2.7736) (-71.4763, -2.7595) knots 0 0 0 0 0 0 0.033333 0.066667 0.1 0.133333 0.166667 0.2 0.233333 0.266667 0.3 0.333333 0.366667 0.4 0.433333 0.466667 0.5 0.533333 0.566667 0.6 0.633333 0.666667 0.7 0.733333 0.766667 0.8 0.833333 0.866667 0.9 0.933333 0.966667 1 1 1 1 1 1
  arc A9 (-71.4763, -2.7595) -> (-72.4412, -3.3569) centre (-54.905, -30.601) ccw
  spline S9 degree 5 poles (-72.4412, -3.3569) (-72.4387, -3.3837) (-72.4336, -3.4372) (-72.4256, -3.5173) (-72.4142, -3.6238) (-72.3988, -3.7564) (-72.3821, -3.8885) (-72.3643, -4.0201) (-72.3451, -4.1512) (-72.3247, -4.2818) (-72.3031, -4.4119) (-72.2802, -4.5414) (-72.256, -4.6703) (-72.2305, -4.7987) (-72.2037, -4.9264) (-72.1754, -5.0534) (-72.1458, -5.1797) (-72.1146, -5.3053) (-72.0819, -5.4301) (-72.0478, -5.5542) (-72.0121, -5.6775) (-71.975, -5.8001) (-71.9363, -5.9218) (-71.896, -6.0427) (-71.854, -6.1626) (-71.81, -6.2813) (-71.7638, -6.3988) (-71.7151, -6.5148) (-71.6638, -6.6292) (-71.6098, -6.7419) (-71.5529, -6.8529) (-71.5052, -6.9403) (-71.4682, -7.0051) (-71.443, -7.0479) (-71.4302, -7.0692) knots 0 0 0 0 0 0 0.033333 0.066667 0.1 0.133333 0.166667 0.2 0.233333 0.266667 0.3 0.333333 0.366667 0.4 0.433333 0.466667 0.5 0.533333 0.566667 0.6 0.633333 0.666667 0.7 0.733333 0.766667 0.8 0.833333 0.866667 0.9 0.933333 0.966667 1 1 1 1 1 1
  line L10 (-71.4302, -7.0692) -> (-71.1977, -7.4003)
  arc A10 (-71.1977, -7.4003) -> (-72.7613, -8.5811) centre (-54.905, -30.601) ccw
  line L11 (-72.7613, -8.5811) -> (-73.0161, -8.2669)
  spline S10 degree 5 poles (-73.0161, -8.2669) (-73.0331, -8.2487) (-73.0674, -8.2127) (-73.1196, -8.1594) (-73.1906, -8.0896) (-73.2818, -8.0046) (-73.3754, -7.9218) (-73.4714, -7.8411) (-73.5697, -7.7626) (-73.67, -7.686) (-73.7722, -7.6111) (-73.876, -7.5379) (-73.9813, -7.4661) (-74.0878, -7.3956) (-74.1955, -7.3263) (-74.3043, -7.2583) (-74.4143, -7.1915) (-74.5254, -7.1259) (-74.6377, -7.0615) (-74.7511, -6.9984) (-74.8655, -6.9365) (-74.981, -6.8757) (-75.0975, -6.8161) (-75.2149, -6.7575) (-75.3331, -6.7001) (-75.4523, -6.6437) (-75.5723, -6.5883) (-75.6932, -6.534) (-75.8149, -6.4808) (-75.9374, -6.4286) (-76.0608, -6.3775) (-76.1601, -6.3374) (-76.2349, -6.3078) (-76.285, -6.2882) (-76.3101, -6.2785) knots 0 0 0 0 0 0 0.033333 0.066667 0.1 0.133333 0.166667 0.2 0.233333 0.266667 0.3 0.333333 0.366667 0.4 0.433333 0.466667 0.5 0.533333 0.566667 0.6 0.633333 0.666667 0.7 0.733333 0.766667 0.8 0.833333 0.866667 0.9 0.933333 0.966667 1 1 1 1 1 1
  arc A11 (-76.3101, -6.2785) -> (-77.1487, -7.0431) centre (-54.905, -30.601) ccw
  spline S11 degree 5 poles (-77.1487, -7.0431) (-77.1414, -7.0689) (-77.1265, -7.1206) (-77.1039, -7.1978) (-77.0732, -7.3004) (-77.0336, -7.4279) (-76.993, -7.5548) (-76.9512, -7.6809) (-76.9083, -7.8062) (-76.8643, -7.9308) (-76.8191, -8.0547) (-76.7728, -8.1778) (-76.7253, -8.3001) (-76.6767, -8.4215) (-76.6268, -8.5421) (-76.5757, -8.6618) (-76.5234, -8.7806) (-76.4696, -8.8983) (-76.4146, -9.015) (-76.3582, -9.1306) (-76.3005, -9.2453) (-76.2415, -9.3589) (-76.1811, -9.4715) (-76.1193, -9.5829) (-76.056, -9.6931) (-75.9909, -9.8017) (-75.9238, -9.9087) (-75.8547, -10.0138) (-75.7832, -10.1168) (-75.7094, -10.2176) (-75.6332, -10.3163) (-75.5702, -10.3934) (-75.5219, -10.4503) (-75.4892, -10.4878) (-75.4728, -10.5064) knots 0 0 0 0 0 0 0.033333 0.066667 0.1 0.133333 0.166667 0.2 0.233333 0.266667 0.3 0.333333 0.366667 0.4 0.433333 0.466667 0.5 0.533333 0.566667 0.6 0.633333 0.666667 0.7 0.733333 0.766667 0.8 0.833333 0.866667 0.9 0.933333 0.966667 1 1 1 1 1 1
  line L12 (-75.4728, -10.5064) -> (-75.1834, -10.7891)
  arc A12 (-75.1834, -10.7891) -> (-76.5034, -12.2371) centre (-54.905, -30.601) ccw
  line L13 (-76.5034, -12.2371) -> (-76.8116, -11.975)
  spline S12 degree 5 poles (-76.8116, -11.975) (-76.8317, -11.9604) (-76.872, -11.9313) (-76.9331, -11.8884) (-77.0157, -11.8329) (-77.121, -11.7661) (-77.2282, -11.7019) (-77.3374, -11.6402) (-77.4484, -11.5811) (-77.5611, -11.5242) (-77.6753, -11.4694) (-77.7908, -11.4165) (-77.9075, -11.3652) (-78.0251, -11.3155) (-78.1437, -11.2672) (-78.2632, -11.2203) (-78.3836, -11.1749) (-78.5049, -11.1308) (-78.6271, -11.0882) (-78.7501, -11.047) (-78.874, -11.0072) (-78.9987, -10.9686) (-79.1241, -10.9314) (-79.2503, -10.8954) (-79.3771, -10.8607) (-79.5046, -10.8271) (-79.6328, -10.7948) (-79.7615, -10.7637) (-79.8909, -10.7337) (-80.021, -10.7049) (-80.1516, -10.6773) (-80.2566, -10.6561) (-80.3356, -10.6408) (-80.3884, -10.6308) (-80.4148, -10.6258) knots 0 0 0 0 0 0 0.033333 0.066667 0.1 0.133333 0.166667 0.2 0.233333 0.266667 0.3 0.333333 0.366667 0.4 0.433333 0.466667 0.5 0.533333 0.566667 0.6 0.633333 0.666667 0.7 0.733333 0.766667 0.8 0.833333 0.866667 0.9 0.933333 0.966667 1 1 1 1 1 1
  arc A13 (-80.4148, -10.6258) -> (-81.0987, -11.5314) centre (-54.905, -30.601) ccw
  spline S13 degree 5 poles (-81.0987, -11.5314) (-81.0868, -11.5555) (-81.0627, -11.6036) (-81.0263, -11.6753) (-80.9772, -11.7705) (-80.9149, -11.8886) (-80.8516, -12.0058) (-80.7874, -12.1221) (-80.7222, -12.2374) (-80.656, -12.3518) (-80.5888, -12.4653) (-80.5207, -12.5778) (-80.4516, -12.6893) (-80.3815, -12.7997) (-80.3103, -12.9091) (-80.2381, -13.0174) (-80.1648, -13.1244) (-80.0903, -13.2303) (-80.0148, -13.3349) (-79.9381, -13.4382) (-79.8603, -13.5403) (-79.7814, -13.6412) (-79.7014, -13.7407) (-79.6202, -13.8389) (-79.5377, -13.9355) (-79.4537, -14.0304) (-79.3682, -14.1232) (-79.2809, -14.2138) (-79.1917, -14.3019) (-79.1006, -14.3875) (-79.0075, -14.4705) (-78.9315, -14.5347) (-78.8736, -14.5818) (-78.8346, -14.6126) (-78.815, -14.6279) knots 0 0 0 0 0 0 0.033333 0.066667 0.1 0.133333 0.166667 0.2 0.233333 0.266667 0.3 0.333333 0.366667 0.4 0.433333 0.466667 0.5 0.533333 0.566667 0.6 0.633333 0.666667 0.7 0.733333 0.766667 0.8 0.833333 0.866667 0.9 0.933333 0.966667 1 1 1 1 1 1
  line L14 (-78.815, -14.6279) -> (-78.4785, -14.8526)
  arc A14 (-78.4785, -14.8526) -> (-79.0087, -15.6766) centre (-54.905, -30.601) ccw
  line L15 (-79.0087, -15.6766) -> (-54.905, -30.601)
  point P0 (-47.9322, -2.0788)
  point P1 (-47.9385, -1.4522)
  point P2 (-47.9936, -0.815)
  point P3 (-48.0903, -0.1698)
  point P4 (-48.2248, 0.4817)
  point P5 (-49.9057, 0.7959)
  point P6 (-50.2665, 0.237)
  point P7 (-50.5898, -0.3297)
  point P8 (-50.8713, -0.904)
  point P9 (-51.1036, -1.486)
  point P10 (-53.2918, -1.2832)
  point P11 (-53.4132, -0.6684)
  point P12 (-53.5844, -0.0522)
  point P13 (-53.7981, 0.5642)
  point P14 (-54.05, 1.1799)
  point P15 (-55.76, 1.1799)
  point P16 (-56.0119, 0.5642)
  point P17 (-56.2256, -0.0522)
  point P18 (-56.3968, -0.6684)
  point P19 (-56.5182, -1.2832)
  point P20 (-58.7064, -1.486)
  point P21 (-58.9387, -0.904)
  point P22 (-59.2202, -0.3297)
  point P23 (-59.5435, 0.237)
  point P24 (-59.9043, 0.7959)
  point P25 (-61.5852, 0.4817)
  point P26 (-61.7197, -0.1698)
  point P27 (-61.8164, -0.815)
  point P28 (-61.8715, -1.4522)
  point P29 (-61.8778, -2.0788)
  point P30 (-63.9916, -2.6802)
  point P31 (-64.3268, -2.1508)
  point P32 (-64.7091, -1.6381)
  point P33 (-65.131, -1.1404)
  point P34 (-65.5883, -0.6573)
  point P35 (-67.1829, -1.275)
  point P36 (-67.1954, -1.9402)
  point P37 (-67.1719, -2.5922)
  point P38 (-67.109, -3.2286)
  point P39 (-67, -3.8457)
  point P40 (-68.9673, -4.8253)
  point P41 (-69.3941, -4.3665)
  point P42 (-69.8641, -3.9327)
  point P43 (-70.3702, -3.5211)
  point P44 (-70.9085, -3.1302)
  point P45 (-72.3625, -4.0304)
  point P46 (-72.2525, -4.6865)
  point P47 (-72.1096, -5.3231)
  point P48 (-71.9308, -5.9371)
  point P49 (-71.7104, -6.5237)
  point P50 (-73.4641, -7.8481)
  point P51 (-73.968, -7.4755)
  point P52 (-74.5097, -7.1355)
  point P53 (-75.0828, -6.8239)
  point P54 (-75.6838, -6.5386)
  point P55 (-76.9476, -7.6906)
  point P56 (-76.7189, -8.3154)
  point P57 (-76.4615, -8.9148)
  point P58 (-76.1729, -9.4856)
  point P59 (-75.8484, -10.0217)
  point P60 (-77.329, -11.6457)
  point P61 (-77.8927, -11.3721)
  point P62 (-78.4876, -11.1374)
  point P63 (-79.1083, -10.9364)
  point P64 (-79.7515, -10.7664)
  point P65 (-80.782, -12.131)
  point P66 (-80.4425, -12.7031)
  point P67 (-80.0793, -13.2451)
  point P68 (-79.6907, -13.7531)
  point P69 (-79.2733, -14.2204)
extrude "X02_add_gear (1)" add sketch "X02_add_gear" along normal blind 9.5 bodies 7 in component "OuterKnuckle_L"
sketch "X03_add_wedge" plane through (-4.75, 0, 0) normal (1, 0, 0) x (0, 0, -1) in component "OuterKnuckle_L"
  line L0 (-54.905, -30.601) -> (-48.3371, -7.5172)
  arc A0 (-48.3371, -7.5172) -> (-78.1921, -24.7949) centre (-54.905, -30.601) ccw
  line L1 (-78.1921, -24.7949) -> (-54.905, -30.601)
extrude "X03_add_wedge (1)" add sketch "X03_add_wedge" along normal blind 9.5 bodies 7 in component "OuterKnuckle_L"
sketch "X04_cut_kidney" plane through (-4.75, 0, 0) normal (1, 0, 0) x (0, 0, -1) in component "OuterKnuckle_L"
  arc A0 (-61.6876, -10.9383) -> (-72.8524, -20.0883) centre (-54.905, -30.601) ccw
  arc A1 (-72.8524, -20.0883) -> (-69.8324, -21.8573) centre (-71.3424, -20.9728) ccw
  arc A2 (-60.5463, -14.2469) -> (-69.8324, -21.8573) centre (-54.905, -30.601) ccw
  arc A3 (-60.5463, -14.2469) -> (-61.6876, -10.9383) centre (-61.117, -12.5926) ccw
extrude "X04_cut_kidney (1)" cut sketch "X04_cut_kidney" along normal blind 9.5 bodies 7 in component "OuterKnuckle_L"
sketch "X05_cut_circle" plane through (-4.75, 0, 0) normal (1, 0, 0) x (0, 0, -1) in component "OuterKnuckle_L"
  circle A0 centre (-54.905, -30.601) radius 1.65
extrude "X05_cut_circle (1)" cut sketch "X05_cut_circle" along normal blind 9.5 bodies 7 in component "OuterKnuckle_L"
sketch "X06_cut_circle (2)" plane through (-4.75, 0, 0) normal (1, 0, 0) x (0, 0, -1) in component "OuterKnuckle_L"
  circle A0 centre (-51.2999, -62.1457) radius 1.65
extrude "X06_cut_circle (1)'" cut sketch "X06_cut_circle (2)" along normal blind 9.5 bodies 7 in component "OuterKnuckle_L"
sketch "X07_cut_circle (3)" plane through (-4.75, 0, 0) normal (1, 0, 0) x (0, 0, -1) in component "OuterKnuckle_L"
  circle A0 centre (-60.539, -65.9718) radius 1.65
extrude "X07_cut_circle (1)''" cut sketch "X07_cut_circle (3)" along normal blind 9.5 bodies 7 in component "OuterKnuckle_L"
ref_plane "WorkPlane1" through (-4.75, 0, 0) normal (1, 0, 0) x (0, 1, 0) in component "OuterKnuckle_R"
sketch "X00_add_circle (3)" plane through (-4.75, 0, 0) normal (1, 0, 0) x (0, 0, -1) in component "OuterKnuckle_R"
  circle A0 centre (-54.905, -30.601) radius 9
extrude "X00_add_circle (1)''" add sketch "X00_add_circle (3)" along normal blind 9.5 separate body makes body 8 in component "OuterKnuckle_R"
sketch "X01_add_hull (2)" plane through (-4.75, 0, 0) normal (1, 0, 0) x (0, 0, -1) in component "OuterKnuckle_R"
  line L0 (-58.2433, -71.5153) -> (-49.0042, -67.6891)
  arc A0 (-49.0042, -67.6891) -> (-45.3076, -61.8413) centre (-51.2999, -62.1457) ccw
  line L1 (-45.3076, -61.8413) -> (-46.9153, -30.1951)
  arc A1 (-46.9153, -30.1951) -> (-62.8633, -29.7857) centre (-54.905, -30.601) ccw
  line L2 (-62.8633, -29.7857) -> (-66.5078, -65.3604)
  arc A2 (-66.5078, -65.3604) -> (-58.2433, -71.5153) centre (-60.539, -65.9718) ccw
extrude "X01_add_hull (1)'" add sketch "X01_add_hull (2)" along normal blind 9.5 bodies 8 in component "OuterKnuckle_R"